Autodesk Fusion 360 part; units mm, degrees
(part 2 of 2)
sketch "Tagli linguette 1,5" plane through (0, 0, 0) normal (0, 0, 1) x (1, 0, 0) in component "Bezel"
  line L0 (-24.4, -37.2) -> (-23.4, -37.2)
  line L1 (-23.4, -37.2) -> (-23.4, -35.5)
  line L2 (-23.4, -35.5) -> (-24.4, -35.5)
  line L3 (-24.4, -35.5) -> (-24.4, -37.2)
  line L4 (-24.4, 71.9) -> (-23.4, 71.9)
  line L5 (-23.4, 71.9) -> (-23.4, 73.6)
  line L6 (-23.4, 73.6) -> (-24.4, 73.6)
  line L7 (-24.4, 73.6) -> (-24.4, 71.9)
  line L8 (-13.4, -37.2) -> (-12.4, -37.2)
  line L9 (-12.4, -37.2) -> (-12.4, -35.5)
  line L10 (-12.4, -35.5) -> (-13.4, -35.5)
  line L11 (-13.4, -35.5) -> (-13.4, -37.2)
  line L12 (-13.4, 71.9) -> (-12.4, 71.9)
  line L13 (-12.4, 71.9) -> (-12.4, 73.6)
  line L14 (-12.4, 73.6) -> (-13.4, 73.6)
  line L15 (-13.4, 73.6) -> (-13.4, 71.9)
  line L16 (55.6, -37.2) -> (56.6, -37.2)
  line L17 (56.6, -37.2) -> (56.6, -35.5)
  line L18 (56.6, -35.5) -> (55.6, -35.5)
  line L19 (55.6, -35.5) -> (55.6, -37.2)
  line L20 (55.6, 71.9) -> (56.6, 71.9)
  line L21 (56.6, 71.9) -> (56.6, 73.6)
  line L22 (56.6, 73.6) -> (55.6, 73.6)
  line L23 (55.6, 73.6) -> (55.6, 71.9)
  line L24 (66.6, -37.2) -> (67.6, -37.2)
  line L25 (67.6, -37.2) -> (67.6, -35.5)
  line L26 (67.6, -35.5) -> (66.6, -35.5)
  line L27 (66.6, -35.5) -> (66.6, -37.2)
  line L28 (66.6, 71.9) -> (67.6, 71.9)
  line L29 (67.6, 71.9) -> (67.6, 73.6)
  line L30 (67.6, 73.6) -> (66.6, 73.6)
  line L31 (66.6, 73.6) -> (66.6, 71.9)
  line L32 (-65.5, -18) -> (-63.8, -18)
  line L33 (-63.8, -18) -> (-63.8, -17)
  line L34 (-63.8, -17) -> (-65.5, -17)
  line L35 (-65.5, -17) -> (-65.5, -18)
  line L36 (107, -18) -> (108.7, -18)
  line L37 (108.7, -18) -> (108.7, -17)
  line L38 (108.7, -17) -> (107, -17)
  line L39 (107, -17) -> (107, -18)
  line L40 (-65.5, -7) -> (-63.8, -7)
  line L41 (-63.8, -7) -> (-63.8, -6)
  line L42 (-63.8, -6) -> (-65.5, -6)
  line L43 (-65.5, -6) -> (-65.5, -7)
  line L44 (107, -7) -> (108.7, -7)
  line L45 (108.7, -7) -> (108.7, -6)
  line L46 (108.7, -6) -> (107, -6)
  line L47 (107, -6) -> (107, -7)
  line L48 (-65.5, 42.4) -> (-63.8, 42.4)
  line L49 (-63.8, 42.4) -> (-63.8, 43.4)
  line L50 (-63.8, 43.4) -> (-65.5, 43.4)
  line L51 (-65.5, 43.4) -> (-65.5, 42.4)
  line L52 (107, 42.4) -> (108.7, 42.4)
  line L53 (108.7, 42.4) -> (108.7, 43.4)
  line L54 (108.7, 43.4) -> (107, 43.4)
  line L55 (107, 43.4) -> (107, 42.4)
  line L56 (-65.5, 53.4) -> (-63.8, 53.4)
  line L57 (-63.8, 53.4) -> (-63.8, 54.4)
  line L58 (-63.8, 54.4) -> (-65.5, 54.4)
  line L59 (-65.5, 54.4) -> (-65.5, 53.4)
  line L60 (107, 53.4) -> (108.7, 53.4)
  line L61 (108.7, 53.4) -> (108.7, 54.4)
  line L62 (108.7, 54.4) -> (107, 54.4)
  line L63 (107, 54.4) -> (107, 53.4)
extrude "Tagli linguette 1,5 (1)" cut sketch "Tagli linguette 1,5" along normal blind 7.1 from surface at 4.4 bodies 2 in component "Bezel"
extrude "Finestra rotellina 1,5'" cut sketch "Finestra rotellina (2)" along normal blind 4.6 from surface at 104.7 bodies 2 in component "Bezel"
chamfer "Smusso invito 1,5" distance 0.45 angle 45 8 edges at (106.8, 48.4, 11.1) (106.8, -12, 11.1) (-18.4, -35.3, 11.1) (61.6, -35.3, 11.1) (-18.4, 71.7, 11.1) (61.6, 71.7, 11.1) (-63.6, -12, 11.1) (-63.6, 48.4, 11.1) tangent chain off on bodies 2 in component "Bezel"
chamfer "Smusso ritenuta 1,5" distance 0.25 angle 45 8 edges at (106.8, 48.4, 9.6) (106.8, -12, 9.6) (-18.4, -35.3, 9.6) (61.6, -35.3, 9.6) (-18.4, 71.7, 9.6) (61.6, 71.7, 9.6) (-63.6, -12, 9.6) (-63.6, 48.4, 9.6) tangent chain off on bodies 2 in component "Bezel"
sketch "Tasche aria retro" plane through (0, 0, 0) normal (0, 0, 1) x (1, 0, 0) in component "Shell"
  line L0 (-12.1, -24) -> (54.5, -24)
  line L1 (54.5, -24) -> (54.5, 26.8)
  line L2 (49.5, 31.8) -> (-7.1, 31.8)
  line L3 (-12.1, 26.8) -> (-12.1, -24)
  arc A0 (54.5, 26.8) -> (49.5, 31.8) centre (49.5, 26.8) ccw
  arc A1 (-7.1, 31.8) -> (-12.1, 26.8) centre (-7.1, 26.8) ccw
  line L4 (-68, 40.8) -> (-19.8, 40.8)
  line L5 (-15.8, 44.8) -> (-15.8, 45.7)
  line L6 (-19.8, 49.7) -> (-22.8, 49.7)
  line L7 (-24.3, 51.2) -> (-24.3, 59.5)
  line L8 (-28.3, 63.5) -> (-68, 63.5)
  line L9 (-68, 63.5) -> (-68, 40.8)
  arc A2 (-19.8, 40.8) -> (-15.8, 44.8) centre (-19.8, 44.8) ccw
  arc A3 (-15.8, 45.7) -> (-19.8, 49.7) centre (-19.8, 45.7) ccw
  arc A4 (-24.3, 51.2) -> (-22.8, 49.7) centre (-22.8, 51.2) ccw
  arc A5 (-24.3, 59.5) -> (-28.3, 63.5) centre (-28.3, 59.5) ccw
  line L10 (60.4, 40.8) -> (111, 40.8)
  line L11 (111, 40.8) -> (111, 63.5)
  line L12 (111, 63.5) -> (71.2, 63.5)
  line L13 (67.2, 59.5) -> (67.2, 51.2)
  line L14 (65.7, 49.7) -> (60.4, 49.7)
  line L15 (56.4, 45.7) -> (56.4, 44.8)
  arc A6 (56.4, 44.8) -> (60.4, 40.8) centre (60.4, 44.8) ccw
  arc A7 (71.2, 63.5) -> (67.2, 59.5) centre (71.2, 59.5) ccw
  arc A8 (65.7, 49.7) -> (67.2, 51.2) centre (65.7, 51.2) ccw
  arc A9 (60.4, 49.7) -> (56.4, 45.7) centre (60.4, 45.7) ccw
  circle A10 centre (-55.85, 64.25) radius 5
  circle A11 centre (99.05, 64.25) radius 5
  constraint tangent L1 A0
  constraint tangent L2 A0
  constraint tangent L2 A1
  constraint tangent L3 A1
  constraint tangent L4 A2
  constraint tangent L5 A2
  constraint tangent L5 A3
  constraint tangent L6 A3
  constraint tangent L6 A4
  constraint tangent L7 A4
  constraint tangent L7 A5
  constraint tangent L8 A5
  constraint tangent L15 A6
  constraint tangent L10 A6
  constraint tangent L12 A7
  constraint tangent L13 A7
  constraint tangent L13 A8
  constraint tangent L14 A8
  constraint tangent L14 A9
  constraint tangent L15 A9
extrude "Tasche aria retro (1)" cut sketch "Tasche aria retro" along normal blind 3 from surface at 40 contours L0 L1 L2 L3 A0 A1 | L4 L5 L6 L7 L8 L9 A2 A3 A4 A5 A10 | L10 L11 L12 L13 L14 L15 A6 A7 A8 A9 A11 bodies 1 in component "Shell"
sketch "Piastra stand" plane through (0, 0, 0) normal (0, 0, 1) x (1, 0, 0) in component "Stand"
  line L0 (-24, 50.5) -> (66.8, 50.5)
  line L1 (66.8, 50.5) -> (66.8, 69)
  line L2 (66.8, 69) -> (-24, 69)
  line L3 (-24, 69) -> (-24, 50.5)
extrude "Piastra stand (1)" add sketch "Piastra stand" along normal blind 4 from surface at 41.5 separate body makes body 5 in component "Stand"
sketch "Perni stand" plane through (0, 0, 0) normal (0, 0, 1) x (1, 0, 0) in component "Stand"
  circle A0 centre (-18.4, 61.8) radius 2
  circle A1 centre (61.6, 61.8) radius 2
extrude "Perni stand (1)" add sketch "Perni stand" along normal blind 3.5 from surface at 38.1 bodies 5 in component "Stand"
sketch "Teste perni stand" plane through (0, 0, 0) normal (0, 0, 1) x (1, 0, 0) in component "Stand"
  circle A0 centre (-18.4, 61.8) radius 4
  circle A1 centre (61.6, 61.8) radius 4
extrude "Teste perni stand (1)" add sketch "Teste perni stand" along normal blind 2.1 from surface at 36.1 bodies 5 in component "Stand"
sketch "Gamba stand" plane through (0, 0, 0) normal (1, 0, 0) x (0, 0, -1) in component "Stand"
  line L0 (-45.4, 69, -18.4) -> (-45.4, 50.5, -18.4)
  line L1 (-45.4, 50.5, -18.4) -> (-80.3589, -14.3637, -18.4)
  line L2 (-80.3589, -14.3637, -18.4) -> (-91.6352, -10.2594, -18.4)
  line L3 (-91.6352, -10.2594, -18.4) -> (-45.4, 69, -18.4)
extrude "Gamba stand (1)" add sketch "Gamba stand" along normal mid plane 6 contours L0 L1 L2 L3 in plane through (-18.4, 0, 0) normal (1, 0, 0) bodies 5 in component "Stand"
sketch "Gamba stand (1)" plane through (0, 0, 0) normal (1, 0, 0) x (0, 0, -1) in component "Stand"
  line L0 (-45.4, 69, 61.6) -> (-45.4, 50.5, 61.6)
  line L1 (-45.4, 50.5, 61.6) -> (-80.3589, -14.3637, 61.6)
  line L2 (-80.3589, -14.3637, 61.6) -> (-91.6352, -10.2594, 61.6)
  line L3 (-91.6352, -10.2594, 61.6) -> (-45.4, 69, 61.6)
extrude "Gamba stand (2)" add sketch "Gamba stand (1)" along normal mid plane 6 contours L0 L1 L2 L3 in plane through (61.6, 0, 0) normal (1, 0, 0) bodies 5 in component "Stand"
sketch "Traversa stand" plane through (0, 0, 0) normal (1, 0, 0) x (0, 0, -1) in component "Stand"
  line L0 (-80.3583, -14.362, 21.6) -> (-91.6346, -10.2577, 21.6)
  line L1 (-91.6346, -10.2577, 21.6) -> (-89.5825, -4.6196, 21.6)
  line L2 (-89.5825, -4.6196, 21.6) -> (-78.3062, -8.7238, 21.6)
  line L3 (-78.3062, -8.7238, 21.6) -> (-80.3583, -14.362, 21.6)
extrude "Traversa stand (1)" add sketch "Traversa stand" along normal mid plane 86 contours L0 L1 L2 L3 in plane through (21.6, 0, 0) normal (1, 0, 0) bodies 5 in component "Stand"
fillet "Raccordo gambe piastra" radius 3 4 edges at (-21.4, 59.6643, 45.5) (58.6, 59.6643, 45.5) (64.6, 59.6643, 45.5) (-15.4, 59.6643, 45.5) on bodies 5 in component "Stand"
fillet "Raccordo gambe traversa" radius 2 4 edges at (-21.4, -4.8053, 89.0722) (64.6, -4.8053, 89.0722) (58.6, -6.8574, 83.4341) (-15.4, -6.8574, 83.4341) on bodies 5 in component "Stand"
sketch "Torretta vite stand" plane through (0, 0, 0) normal (0, 0, 1) x (1, 0, 0) in component "Shell"
  circle A0 centre (21.6, 60) radius 4
extrude "Torretta vite stand (1)" add sketch "Torretta vite stand" along normal blind 9.1 from surface at 29.5 bodies 1 in component "Shell"
fillet "Raccordo torretta stand" radius 1.5 1 edges at (17.8707, 58.5535, 38.5) on bodies 1 in component "Shell"
sketch "Foro vite stand" plane through (0, 0, 0) normal (0, 0, 1) x (1, 0, 0) in component "Shell"
  circle A0 centre (21.6, 60) radius 1.25
extrude "Foro vite stand (1)" cut sketch "Foro vite stand" along normal blind 12.2 from surface at 29.4 bodies 1 in component "Shell"
thread "Filetto M3 stand" "ISO Metric profile 3.0 M3x0.5 M3x0.5 6H" major diameter 3.086 minor diameter 2.529 pitch 0.5 angle 60 modelled right hand crest width 0.1368 on face at (20.4482, 60.4855, 37.5) crest through (22.8645, 60, 29.625) on bodies 1 in component "Shell"
sketch "Foro passante vite" plane through (0, 0, 0) normal (0, 0, 1) x (1, 0, 0) in component "Stand"
  circle A0 centre (21.6, 60) radius 1.7
extrude "Foro passante vite (1)" cut sketch "Foro passante vite" along normal blind 4.3 from surface at 41.4 bodies 5 in component "Stand"
sketch "Finestra display 2" plane through (0, 0, 0) normal (0, 0, 1) x (1, 0, 0) in component "Bezel"
  line L0 (-54.02, -23.27) -> (101.72, -23.27)
  arc A0 (101.72, -23.27) -> (103.22, -21.77) centre (101.72, -21.77) ccw
  line L1 (103.22, -21.77) -> (103.22, 66.67)
  arc A1 (103.22, 66.67) -> (101.72, 68.17) centre (101.72, 66.67) ccw
  line L2 (101.72, 68.17) -> (-54.02, 68.17)
  arc A2 (-54.02, 68.17) -> (-55.52, 66.67) centre (-54.02, 66.67) ccw
  line L3 (-55.52, 66.67) -> (-55.52, -21.77)
  arc A3 (-55.52, -21.77) -> (-54.02, -23.27) centre (-54.02, -21.77) ccw
extrude "Finestra display 2 (1)" cut sketch "Finestra display 2" along normal blind 2.7 from surface at 0.82 bodies 2 in component "Bezel"
other "Base Mesh Feature3"
other "Base Mesh Feature4"
other "Base Mesh Feature5"
other "Base Mesh Feature6"
component "Shell" placed x (1, 0, 0) y (0, 1, 0) z (0, 0, 1) at (0, 0, 0)
component "Bezel" placed x (1, 0, 0) y (0, 1, 0) z (0, 0, 1) at (0, 0, 0)
component "Stand" placed x (1, 0, 0) y (0, 1, 0) z (0, 0, 1) at (0, 0, 0)
equation "d59 = 15.2779653276 mm"
equation "d63 = d59 - 11.86 mm"
named bodies: "Shell", "Bezel", "Shell (1)", "Shell (2)", "Stand"
